Autodesk Fusion 360 part; units mm, degrees
(part 2 of 2)
extrude "E84 PCB stand-off pads - 4.2mm underside clearance" add sketch "スケッチ3 (2)" along normal blind 4.2 bodies 63 in component "Electronics carrier - PSoC Edge E84 AI + M5Stack Basic"
ref_plane "作業平面3" through (0, 0, 2.8) normal (0, 0, 1) x (1, 0, 0) in component "Electronics carrier - PSoC Edge E84 AI + M5Stack Basic"
sketch "スケッチ4 (2)" plane through (0, 0, 2.8) normal (0, 0, 1) x (1, 0, 0) in component "Electronics carrier - PSoC Edge E84 AI + M5Stack Basic"
  line L0 (-70, -30) -> (-39, -30)
  line L1 (-39, -30) -> (-39, -28)
  line L2 (-39, -28) -> (-70, -28)
  line L3 (-70, -28) -> (-70, -30)
  line L4 (-27, -30) -> (4, -30)
  line L5 (4, -30) -> (4, -28)
  line L6 (4, -28) -> (-27, -28)
  line L7 (-27, -28) -> (-27, -30)
  line L8 (-70, 28) -> (-39, 28)
  line L9 (-39, 28) -> (-39, 30)
  line L10 (-39, 30) -> (-70, 30)
  line L11 (-70, 30) -> (-70, 28)
  line L12 (-27, 28) -> (4, 28)
  line L13 (4, 28) -> (4, 30)
  line L14 (4, 30) -> (-27, 30)
  line L15 (-27, 30) -> (-27, 28)
extrude "E84 side guides with open USB and header ends" add sketch "スケッチ4 (2)" along normal blind 3.5 bodies 63 in component "Electronics carrier - PSoC Edge E84 AI + M5Stack Basic"
ref_plane "作業平面4" through (0, 0, 2.8) normal (0, 0, 1) x (1, 0, 0) in component "Electronics carrier - PSoC Edge E84 AI + M5Stack Basic"
sketch "スケッチ5 (2)" plane through (0, 0, 2.8) normal (0, 0, 1) x (1, 0, 0) in component "Electronics carrier - PSoC Edge E84 AI + M5Stack Basic"
  line L0 (18, -29) -> (20, -29)
  line L1 (20, -29) -> (20, -12)
  line L2 (20, -12) -> (18, -12)
  line L3 (18, -12) -> (18, -29)
  line L4 (18, 12) -> (20, 12)
  line L5 (20, 12) -> (20, 29)
  line L6 (20, 29) -> (18, 29)
  line L7 (18, 29) -> (18, 12)
  line L8 (80, -29) -> (82, -29)
  line L9 (82, -29) -> (82, -12)
  line L10 (82, -12) -> (80, -12)
  line L11 (80, -12) -> (80, -29)
  line L12 (80, 12) -> (82, 12)
  line L13 (82, 12) -> (82, 29)
  line L14 (82, 29) -> (80, 29)
  line L15 (80, 29) -> (80, 12)
  line L16 (20, -32) -> (38, -32)
  line L17 (38, -32) -> (38, -30)
  line L18 (38, -30) -> (20, -30)
  line L19 (20, -30) -> (20, -32)
  line L20 (62, -32) -> (80, -32)
  line L21 (80, -32) -> (80, -30)
  line L22 (80, -30) -> (62, -30)
  line L23 (62, -30) -> (62, -32)
  line L24 (20, 30) -> (38, 30)
  line L25 (38, 30) -> (38, 32)
  line L26 (38, 32) -> (20, 32)
  line L27 (20, 32) -> (20, 30)
  line L28 (62, 30) -> (80, 30)
  line L29 (80, 30) -> (80, 32)
  line L30 (80, 32) -> (62, 32)
  line L31 (62, 32) -> (62, 30)
extrude "M5Stack Basic retaining fence - connectors accessible" add sketch "スケッチ5 (2)" along normal blind 7 bodies 63 in component "Electronics carrier - PSoC Edge E84 AI + M5Stack Basic"
component "VS-MGE20 Case Assembly" placed x (1, 0, 0) y (0, 1, 0) z (0, 0, 1) at (0, 0, 0)
component "Electronics carrier - PSoC Edge E84 AI + M5Stack Basic" placed x (1, 0, 0) y (0, 1, 0) z (0, 0, 1) at (0, 0, -27.2)
component "PRINT 01 Front guard" placed x (1, 0, 0) y (0, 1, 0) z (0, 0, 1) at (0, 0, 0) in component "VS-MGE20 Case Assembly"
component "PRINT 02 Upper bridge" placed x (1, 0, 0) y (0, 1, 0) z (0, 0, 1) at (0, 0, 0) in component "VS-MGE20 Case Assembly"
component "PRINT 03 Lower bridge" placed x (1, 0, 0) y (0, 1, 0) z (0, 0, 1) at (0, 0, 0) in component "VS-MGE20 Case Assembly"
component "PRINT 04 Call servo pod base" placed x (1, 0, 0) y (0, 1, 0) z (0, 0, 1) at (0, 0, 0) in component "VS-MGE20 Case Assembly"
component "PRINT 05 End servo pod base" placed x (1, 0, 0) y (0, 1, 0) z (0, 0, 1) at (0, 0, 0) in component "VS-MGE20 Case Assembly"
component "PRINT 06 Call pod retainer" placed x (1, 0, 0) y (0, 1, 0) z (0, 0, 1) at (0, 0, 0) in component "VS-MGE20 Case Assembly"
component "PRINT 07 End pod retainer" placed x (1, 0, 0) y (0, 1, 0) z (0, 0, 1) at (0, 0, 0) in component "VS-MGE20 Case Assembly"
component "PRINT 08 Charger cradle frame" placed x (1, 0, 0) y (0, 1, 0) z (0, 0, 1) at (0, 0, 0) in component "VS-MGE20 Case Assembly"
component "PRINT 09 Call pusher shaft" placed x (1, 0, 0) y (0, 1, 0) z (0, 0, 1) at (0, 0, 0) in component "VS-MGE20 Case Assembly"
component "PRINT 10 Call stop collar" placed x (1, 0, 0) y (0, 1, 0) z (0, 0, 1) at (0, 0, 0) in component "VS-MGE20 Case Assembly"
component "PRINT 11 Call guide ring" placed x (1, 0, 0) y (0, 1, 0) z (0, 0, 1) at (0, 0, 0) in component "VS-MGE20 Case Assembly"
component "PRINT 12 End pusher shaft" placed x (1, 0, 0) y (0, 1, 0) z (0, 0, 1) at (0, 0, 0) in component "VS-MGE20 Case Assembly"
component "PRINT 13 End stop collar" placed x (1, 0, 0) y (0, 1, 0) z (0, 0, 1) at (0, 0, 0) in component "VS-MGE20 Case Assembly"
component "PRINT 14 End guide ring" placed x (1, 0, 0) y (0, 1, 0) z (0, 0, 1) at (0, 0, 0) in component "VS-MGE20 Case Assembly"
component "PRINT 15 Call servo horn" placed x (1, 0, 0) y (0, 1, 0) z (0, 0, 1) at (0, 0, 0) in component "VS-MGE20 Case Assembly"
component "PRINT 16 End servo horn" placed x (1, 0, 0) y (0, 1, 0) z (0, 0, 1) at (0, 0, 0) in component "VS-MGE20 Case Assembly"
component "PRINT 17 Call servo arm HOME" placed x (1, 0, 0) y (0, 1, 0) z (0, 0, 1) at (0, 0, 0) in component "VS-MGE20 Case Assembly"
component "PRINT 18 End servo arm HOME" placed x (1, 0, 0) y (0, 1, 0) z (0, 0, 1) at (0, 0, 0) in component "VS-MGE20 Case Assembly"
component "PRINT 19 Call fork cheek A" placed x (1, 0, 0) y (0, 1, 0) z (0, 0, 1) at (0, 0, 0) in component "VS-MGE20 Case Assembly"
component "PRINT 20 Call fork cheek B" placed x (1, 0, 0) y (0, 1, 0) z (0, 0, 1) at (0, 0, 0) in component "VS-MGE20 Case Assembly"
component "PRINT 21 End fork cheek A" placed x (1, 0, 0) y (0, 1, 0) z (0, 0, 1) at (0, 0, 0) in component "VS-MGE20 Case Assembly"
component "PRINT 22 End fork cheek B" placed x (1, 0, 0) y (0, 1, 0) z (0, 0, 1) at (0, 0, 0) in component "VS-MGE20 Case Assembly"
component "PRINT 23 Call follower pin" placed x (1, 0, 0) y (0, 1, 0) z (0, 0, 1) at (0, 0, 0) in component "VS-MGE20 Case Assembly"
component "PRINT 24 End follower pin" placed x (1, 0, 0) y (0, 1, 0) z (0, 0, 1) at (0, 0, 0) in component "VS-MGE20 Case Assembly"
component "TPU 01 Call button pad" placed x (1, 0, 0) y (0, 1, 0) z (0, 0, 1) at (0, 0, 0) in component "VS-MGE20 Case Assembly"
component "TPU 02 End button pad" placed x (1, 0, 0) y (0, 1, 0) z (0, 0, 1) at (0, 0, 0) in component "VS-MGE20 Case Assembly"
component "REFERENCE ONLY - DO NOT PRINT" placed x (1, 0, 0) y (0, 1, 0) z (0, 0, 1) at (0, 0, 0) in component "VS-MGE20 Case Assembly"
hidden bodies 57 58 59 60
equation "d7 = -( 6.00 mm )"
equation "d253 = -( 2.00 mm )"
equation "d257 = -( 2.00 mm )"
equation "d275 = -( 2.00 mm )"
equation "d279 = -( 2.00 mm )"
equation "d377 = -( 14.00 mm )"
equation "d385 = -( 14.00 mm )"
equation "d427 = -( 3.30 mm )"
named bodies: "SG90 mount Call", "SG90 mount End", "E84 AI plus M5Stack carrier"
